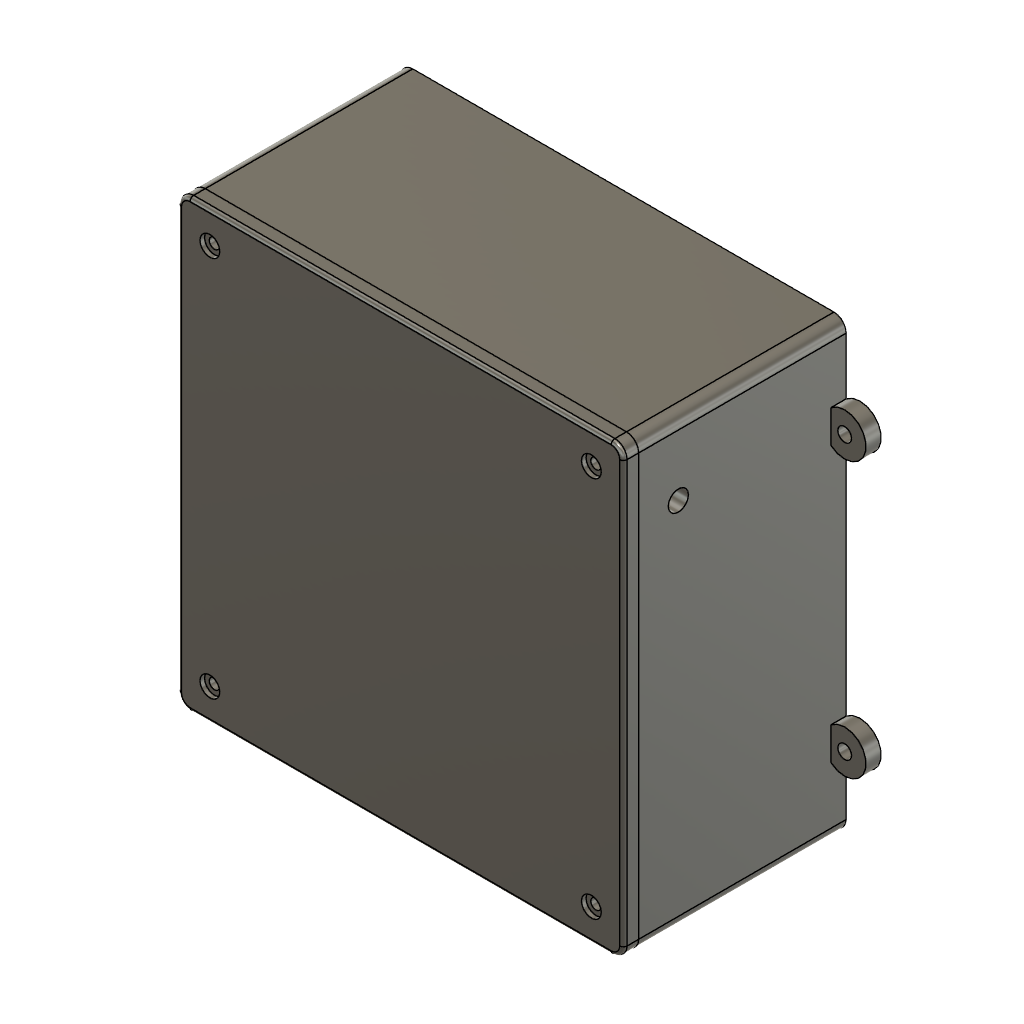
box-hybrid-lora_v1.0.0 (Autodesk Fusion 360 design; units mm, degrees)
part number: 2026-10-20-17-32-16-091
part number: 2026-10-20-17-32-16-274
part number: 2026-10-20-17-32-18-311
Autodesk Fusion 360 part; units mm, degrees
sketch "Outside footprint" plane through (0, 0, 0) normal (0, 0, 1) x (1, 0, 0) in component "01 Body - antenna, gasket groove and fasteners"
  line L0 (0, 0) -> (146, 0)
  line L1 (146, 0) -> (146, 146)
  line L2 (146, 146) -> (0, 146)
  line L3 (0, 146) -> (0, 0)
  dimension "d26" = 146
  dimension "d27" = 146
  constraint coincident L0.start L3.end
  measures "d26" horizontal distance of L0.start L0.end
  measures "d27" vertical distance of L0.end L1.end
extrude "Body outside" add sketch "Outside footprint" along normal blind 68 makes body 1 in component "01 Body - antenna, gasket groove and fasteners"
fillet "Four outside corner fillets" radius 4 4 edges at (0, 146, 34) (146, 146, 34) (146, 0, 34) (0, 0, 34) on bodies 1 in component "01 Body - antenna, gasket groove and fasteners"
shell "Open body - 5 mm walls and bottom" thickness 5 removed faces 1 at (94.6667, 50, 68) on bodies 1 in component "01 Body - antenna, gasket groove and fasteners"
ref_plane "WorkPlane1" through (0, 0, 64) normal (0, 0, 1) x (1, 0, 0) in component "01 Body - antenna, gasket groove and fasteners"
sketch "Rim supports screw posts and gasket channel" plane through (0, 0, 64) normal (0, 0, 1) x (1, 0, 0) in component "01 Body - antenna, gasket groove and fasteners"
  line L0 (2, 2) -> (144, 2)
  line L1 (144, 2) -> (144, 144)
  line L2 (144, 144) -> (2, 144)
  line L3 (2, 144) -> (2, 2)
  line L4 (20, 20) -> (126, 20)
  line L5 (126, 20) -> (126, 126)
  line L6 (126, 126) -> (20, 126)
  line L7 (20, 126) -> (20, 20)
extrude "Internal rim with 106 mm PCB insertion opening" add sketch "Rim supports screw posts and gasket channel" along normal blind 4 bodies 1 in component "01 Body - antenna, gasket groove and fasteners"
ref_plane "WorkPlane2" through (0, 0, 68) normal (0, 0, 1) x (1, 0, 0) in component "01 Body - antenna, gasket groove and fasteners"
sketch "Gasket channel - provisional 2 mm cord" plane through (0, 0, 68) normal (0, 0, 1) x (1, 0, 0) in component "01 Body - antenna, gasket groove and fasteners"
  line L0 (16.2, 16.2) -> (129.8, 16.2)
  line L1 (129.8, 16.2) -> (129.8, 129.8)
  line L2 (129.8, 129.8) -> (16.2, 129.8)
  line L3 (16.2, 129.8) -> (16.2, 16.2)
  line L4 (18.4, 18.4) -> (127.6, 18.4)
  line L5 (127.6, 18.4) -> (127.6, 127.6)
  line L6 (127.6, 127.6) -> (18.4, 127.6)
  line L7 (18.4, 127.6) -> (18.4, 18.4)
extrude "Continuous gasket groove in body rim" cut sketch "Gasket channel - provisional 2 mm cord" against normal blind 1.5 bodies 1 in component "01 Body - antenna, gasket groove and fasteners"
sketch "Mount 1 footprint - provisional X" plane through (0, 0, 0) normal (0, 0, 1) x (1, 0, 0) in component "01 Body - antenna, gasket groove and fasteners"
  circle A0 centre (25.436, 25.436) radius 2.5
  dimension "d41" = 5
  measures "d41" diameter of A0
extrude "PCB boss 1 - outside diameter 5 mm" add sketch "Mount 1 footprint - provisional X" along normal blind 10 bodies 1 in component "01 Body - antenna, gasket groove and fasteners"
sketch "Mount 2 footprint - provisional X" plane through (0, 0, 0) normal (0, 0, 1) x (1, 0, 0) in component "01 Body - antenna, gasket groove and fasteners"
  circle A0 centre (120.564, 25.436) radius 2.5
  dimension "d44" = 5
  measures "d44" diameter of A0
extrude "PCB boss 2 - outside diameter 5 mm" add sketch "Mount 2 footprint - provisional X" along normal blind 10 bodies 1 in component "01 Body - antenna, gasket groove and fasteners"
sketch "Mount 3 footprint - provisional X" plane through (0, 0, 0) normal (0, 0, 1) x (1, 0, 0) in component "01 Body - antenna, gasket groove and fasteners"
  circle A0 centre (25.436, 120.115) radius 2.5
  dimension "d47" = 5
  measures "d47" diameter of A0
extrude "PCB boss 3 - outside diameter 5 mm" add sketch "Mount 3 footprint - provisional X" along normal blind 10 bodies 1 in component "01 Body - antenna, gasket groove and fasteners"
sketch "Mount 4 footprint - provisional X" plane through (0, 0, 0) normal (0, 0, 1) x (1, 0, 0) in component "01 Body - antenna, gasket groove and fasteners"
  circle A0 centre (120.564, 120.115) radius 2.5
  dimension "d50" = 5
  measures "d50" diameter of A0
extrude "PCB boss 4 - outside diameter 5 mm" add sketch "Mount 4 footprint - provisional X" along normal blind 10 bodies 1 in component "01 Body - antenna, gasket groove and fasteners"
ref_plane "WorkPlane3" through (0, 0, 10) normal (0, 0, 1) x (1, 0, 0) in component "01 Body - antenna, gasket groove and fasteners"
sketch "Mount 1 blind hole" plane through (0, 0, 10) normal (0, 0, 1) x (1, 0, 0) in component "01 Body - antenna, gasket groove and fasteners"
  circle A0 centre (25.436, 25.436) radius 1
  dimension "d55" = 2
  measures "d55" diameter of A0
extrude "PCB hole 1 - diameter 2 mm, blind" cut sketch "Mount 1 blind hole" against normal blind 4 bodies 1 in component "01 Body - antenna, gasket groove and fasteners"
sketch "Mount 2 blind hole" plane through (0, 0, 10) normal (0, 0, 1) x (1, 0, 0) in component "01 Body - antenna, gasket groove and fasteners"
  circle A0 centre (120.564, 25.436) radius 1
  dimension "d58" = 2
  measures "d58" diameter of A0
extrude "PCB hole 2 - diameter 2 mm, blind" cut sketch "Mount 2 blind hole" against normal blind 4 bodies 1 in component "01 Body - antenna, gasket groove and fasteners"
sketch "Mount 3 blind hole" plane through (0, 0, 10) normal (0, 0, 1) x (1, 0, 0) in component "01 Body - antenna, gasket groove and fasteners"
  circle A0 centre (25.436, 120.115) radius 1
  dimension "d61" = 2
  measures "d61" diameter of A0
extrude "PCB hole 3 - diameter 2 mm, blind" cut sketch "Mount 3 blind hole" against normal blind 4 bodies 1 in component "01 Body - antenna, gasket groove and fasteners"
sketch "Mount 4 blind hole" plane through (0, 0, 10) normal (0, 0, 1) x (1, 0, 0) in component "01 Body - antenna, gasket groove and fasteners"
  circle A0 centre (120.564, 120.115) radius 1
  dimension "d64" = 2
  measures "d64" diameter of A0
extrude "PCB hole 4 - diameter 2 mm, blind" cut sketch "Mount 4 blind hole" against normal blind 4 bodies 1 in component "01 Body - antenna, gasket groove and fasteners"
sketch "Lid screw post 1 footprint" plane through (0, 0, 0) normal (0, 0, 1) x (1, 0, 0) in component "01 Body - antenna, gasket groove and fasteners"
  circle A0 centre (10.5, 10.5) radius 4.5
  dimension "d67" = 9
  measures "d67" diameter of A0
extrude "Lid screw post 1" add sketch "Lid screw post 1 footprint" along normal blind 68 bodies 1 in component "01 Body - antenna, gasket groove and fasteners"
sketch "Lid screw post 2 footprint" plane through (0, 0, 0) normal (0, 0, 1) x (1, 0, 0) in component "01 Body - antenna, gasket groove and fasteners"
  circle A0 centre (135.5, 10.5) radius 4.5
  dimension "d70" = 9
  measures "d70" diameter of A0
extrude "Lid screw post 2" add sketch "Lid screw post 2 footprint" along normal blind 68 bodies 1 in component "01 Body - antenna, gasket groove and fasteners"
sketch "Lid screw post 3 footprint" plane through (0, 0, 0) normal (0, 0, 1) x (1, 0, 0) in component "01 Body - antenna, gasket groove and fasteners"
  circle A0 centre (10.5, 135.5) radius 4.5
  dimension "d73" = 9
  measures "d73" diameter of A0
extrude "Lid screw post 3" add sketch "Lid screw post 3 footprint" along normal blind 68 bodies 1 in component "01 Body - antenna, gasket groove and fasteners"
sketch "Lid screw post 4 footprint" plane through (0, 0, 0) normal (0, 0, 1) x (1, 0, 0) in component "01 Body - antenna, gasket groove and fasteners"
  circle A0 centre (135.5, 135.5) radius 4.5
  dimension "d76" = 9
  measures "d76" diameter of A0
extrude "Lid screw post 4" add sketch "Lid screw post 4 footprint" along normal blind 68 bodies 1 in component "01 Body - antenna, gasket groove and fasteners"
ref_plane "WorkPlane4" through (0, 0, 68) normal (0, 0, 1) x (1, 0, 0) in component "01 Body - antenna, gasket groove and fasteners"
sketch "Lid screw pilot 1" plane through (0, 0, 68) normal (0, 0, 1) x (1, 0, 0) in component "01 Body - antenna, gasket groove and fasteners"
  circle A0 centre (10.5, 10.5) radius 1.25
  dimension "d81" = 2.5
  measures "d81" diameter of A0
extrude "Lid screw blind pilot 1" cut sketch "Lid screw pilot 1" against normal blind 12 bodies 1 in component "01 Body - antenna, gasket groove and fasteners"
sketch "Lid screw pilot 2" plane through (0, 0, 68) normal (0, 0, 1) x (1, 0, 0) in component "01 Body - antenna, gasket groove and fasteners"
  circle A0 centre (135.5, 10.5) radius 1.25
  dimension "d84" = 2.5
  measures "d84" diameter of A0
extrude "Lid screw blind pilot 2" cut sketch "Lid screw pilot 2" against normal blind 12 bodies 1 in component "01 Body - antenna, gasket groove and fasteners"
sketch "Lid screw pilot 3" plane through (0, 0, 68) normal (0, 0, 1) x (1, 0, 0) in component "01 Body - antenna, gasket groove and fasteners"
  circle A0 centre (10.5, 135.5) radius 1.25
  dimension "d87" = 2.5
  measures "d87" diameter of A0
extrude "Lid screw blind pilot 3" cut sketch "Lid screw pilot 3" against normal blind 12 bodies 1 in component "01 Body - antenna, gasket groove and fasteners"
sketch "Lid screw pilot 4" plane through (0, 0, 68) normal (0, 0, 1) x (1, 0, 0) in component "01 Body - antenna, gasket groove and fasteners"
  circle A0 centre (135.5, 135.5) radius 1.25
  dimension "d90" = 2.5
  measures "d90" diameter of A0
extrude "Lid screw blind pilot 4" cut sketch "Lid screw pilot 4" against normal blind 12 bodies 1 in component "01 Body - antenna, gasket groove and fasteners"
sketch "Outer mounting ear 1" plane through (0, 0, 0) normal (0, 0, 1) x (1, 0, 0) in component "01 Body - antenna, gasket groove and fasteners"
  circle A0 centre (-4.5, 28) radius 7
  dimension "d93" = 14
  measures "d93" diameter of A0
extrude "Mounting ear 1" add sketch "Outer mounting ear 1" along normal blind 5 bodies 1 in component "01 Body - antenna, gasket groove and fasteners"
sketch "Outer mounting ear 2" plane through (0, 0, 0) normal (0, 0, 1) x (1, 0, 0) in component "01 Body - antenna, gasket groove and fasteners"
  circle A0 centre (-4.5, 118) radius 7
  dimension "d96" = 14
  measures "d96" diameter of A0
extrude "Mounting ear 2" add sketch "Outer mounting ear 2" along normal blind 5 bodies 1 in component "01 Body - antenna, gasket groove and fasteners"
sketch "Outer mounting ear 3" plane through (0, 0, 0) normal (0, 0, 1) x (1, 0, 0) in component "01 Body - antenna, gasket groove and fasteners"
  circle A0 centre (150.5, 28) radius 7
  dimension "d99" = 14
  measures "d99" diameter of A0
extrude "Mounting ear 3" add sketch "Outer mounting ear 3" along normal blind 5 bodies 1 in component "01 Body - antenna, gasket groove and fasteners"
sketch "Outer mounting ear 4" plane through (0, 0, 0) normal (0, 0, 1) x (1, 0, 0) in component "01 Body - antenna, gasket groove and fasteners"
  circle A0 centre (150.5, 118) radius 7
  dimension "d102" = 14
  measures "d102" diameter of A0
extrude "Mounting ear 4" add sketch "Outer mounting ear 4" along normal blind 5 bodies 1 in component "01 Body - antenna, gasket groove and fasteners"
ref_plane "WorkPlane5" through (0, 0, 5) normal (0, 0, 1) x (1, 0, 0) in component "01 Body - antenna, gasket groove and fasteners"
sketch "Outer mounting hole 1" plane through (0, 0, 5) normal (0, 0, 1) x (1, 0, 0) in component "01 Body - antenna, gasket groove and fasteners"
  circle A0 centre (-4.5, 28) radius 2.25
  dimension "d107" = 4.5
  measures "d107" diameter of A0
extrude "Ear through hole 1" cut sketch "Outer mounting hole 1" against normal blind 5 bodies 1 in component "01 Body - antenna, gasket groove and fasteners"
sketch "Outer mounting hole 2" plane through (0, 0, 5) normal (0, 0, 1) x (1, 0, 0) in component "01 Body - antenna, gasket groove and fasteners"
  circle A0 centre (-4.5, 118) radius 2.25
  dimension "d110" = 4.5
  measures "d110" diameter of A0
extrude "Ear through hole 2" cut sketch "Outer mounting hole 2" against normal blind 5 bodies 1 in component "01 Body - antenna, gasket groove and fasteners"
sketch "Outer mounting hole 3" plane through (0, 0, 5) normal (0, 0, 1) x (1, 0, 0) in component "01 Body - antenna, gasket groove and fasteners"
  circle A0 centre (150.5, 28) radius 2.25
  dimension "d113" = 4.5
  measures "d113" diameter of A0
extrude "Ear through hole 3" cut sketch "Outer mounting hole 3" against normal blind 5 bodies 1 in component "01 Body - antenna, gasket groove and fasteners"
sketch "Outer mounting hole 4" plane through (0, 0, 5) normal (0, 0, 1) x (1, 0, 0) in component "01 Body - antenna, gasket groove and fasteners"
  circle A0 centre (150.5, 118) radius 2.25
  dimension "d116" = 4.5
  measures "d116" diameter of A0
extrude "Ear through hole 4" cut sketch "Outer mounting hole 4" against normal blind 5 bodies 1 in component "01 Body - antenna, gasket groove and fasteners"
ref_plane "WorkPlane6" through (146, 0, 0) normal (1, 0, 0) x (0, 1, 0) in component "01 Body - antenna, gasket groove and fasteners"
sketch "SMA bulkhead at upper right - test opening" plane through (146, 0, 0) normal (1, 0, 0) x (0, 0, -1) in component "01 Body - antenna, gasket groove and fasteners"
  circle A0 centre (-55, 122) radius 3.3
  dimension "d121" = 6.6
  measures "d121" diameter of A0
extrude "SMA bulkhead through wall - test fit" cut sketch "SMA bulkhead at upper right - test opening" along normal mid plane 10 bodies 1 in component "01 Body - antenna, gasket groove and fasteners"
sketch "Lid footprint" plane through (0, 0, 0) normal (0, 0, 1) x (1, 0, 0) in component "02 Lid - rounded top and four screw holes"
  line L0 (0, 0) -> (146, 0)
  line L1 (146, 0) -> (146, 146)
  line L2 (146, 146) -> (0, 146)
  line L3 (0, 146) -> (0, 0)
  dimension "d124" = 146
  dimension "d125" = 146
  constraint coincident L0.start L3.end
  measures "d124" horizontal distance of L0.start L0.end
  measures "d125" vertical distance of L0.end L1.end
extrude "Flat lid placeholder" add sketch "Lid footprint" along normal blind 5 separate body makes body 2 in component "02 Lid - rounded top and four screw holes"
fillet "Four outside corner fillets'" radius 4 4 edges at (0, 146, 2.5) (146, 146, 2.5) (146, 0, 2.5) (0, 0, 2.5) on bodies 2 in component "02 Lid - rounded top and four screw holes"
fillet "Soft rounded top edge of lid" radius 1.2 8 edges at (1.1716, 1.1716, 5) (0, 73, 5) (73, 0, 5) (144.8284, 1.1716, 5) (146, 73, 5) (144.8284, 144.8284, 5) (73, 146, 5) (1.1716, 144.8284, 5) on bodies 2 in component "02 Lid - rounded top and four screw holes"
ref_plane "WorkPlane1" through (0, 0, 5) normal (0, 0, 1) x (1, 0, 0) in component "02 Lid - rounded top and four screw holes"
sketch "Lid clearance hole 1" plane through (0, 0, 5) normal (0, 0, 1) x (1, 0, 0) in component "02 Lid - rounded top and four screw holes"
  circle A0 centre (10.5, 10.5) radius 1.7
  dimension "d134" = 3.4
  measures "d134" diameter of A0
extrude "Lid screw through hole 1" cut sketch "Lid clearance hole 1" against normal blind 5 bodies 2 in component "02 Lid - rounded top and four screw holes"
sketch "Lid screw head recess 1" plane through (0, 0, 5) normal (0, 0, 1) x (1, 0, 0) in component "02 Lid - rounded top and four screw holes"
  circle A0 centre (10.5, 10.5) radius 3.25
  dimension "d137" = 6.5
  measures "d137" diameter of A0
extrude "Lid screw head recess 1 (1)" cut sketch "Lid screw head recess 1" against normal blind 1.5 bodies 2 in component "02 Lid - rounded top and four screw holes"
sketch "Lid clearance hole 2" plane through (0, 0, 5) normal (0, 0, 1) x (1, 0, 0) in component "02 Lid - rounded top and four screw holes"
  circle A0 centre (135.5, 10.5) radius 1.7
  dimension "d140" = 3.4
  measures "d140" diameter of A0
extrude "Lid screw through hole 2" cut sketch "Lid clearance hole 2" against normal blind 5 bodies 2 in component "02 Lid - rounded top and four screw holes"
sketch "Lid screw head recess 2" plane through (0, 0, 5) normal (0, 0, 1) x (1, 0, 0) in component "02 Lid - rounded top and four screw holes"
  circle A0 centre (135.5, 10.5) radius 3.25
  dimension "d143" = 6.5
  measures "d143" diameter of A0
extrude "Lid screw head recess 2 (1)" cut sketch "Lid screw head recess 2" against normal blind 1.5 bodies 2 in component "02 Lid - rounded top and four screw holes"
sketch "Lid clearance hole 3" plane through (0, 0, 5) normal (0, 0, 1) x (1, 0, 0) in component "02 Lid - rounded top and four screw holes"
  circle A0 centre (10.5, 135.5) radius 1.7
  dimension "d146" = 3.4
  measures "d146" diameter of A0
extrude "Lid screw through hole 3" cut sketch "Lid clearance hole 3" against normal blind 5 bodies 2 in component "02 Lid - rounded top and four screw holes"
sketch "Lid screw head recess 3" plane through (0, 0, 5) normal (0, 0, 1) x (1, 0, 0) in component "02 Lid - rounded top and four screw holes"
  circle A0 centre (10.5, 135.5) radius 3.25
  dimension "d149" = 6.5
  measures "d149" diameter of A0
extrude "Lid screw head recess 3 (1)" cut sketch "Lid screw head recess 3" against normal blind 1.5 bodies 2 in component "02 Lid - rounded top and four screw holes"
sketch "Lid clearance hole 4" plane through (0, 0, 5) normal (0, 0, 1) x (1, 0, 0) in component "02 Lid - rounded top and four screw holes"
  circle A0 centre (135.5, 135.5) radius 1.7
  dimension "d152" = 3.4
  measures "d152" diameter of A0
extrude "Lid screw through hole 4" cut sketch "Lid clearance hole 4" against normal blind 5 bodies 2 in component "02 Lid - rounded top and four screw holes"
sketch "Lid screw head recess 4" plane through (0, 0, 5) normal (0, 0, 1) x (1, 0, 0) in component "02 Lid - rounded top and four screw holes"
  circle A0 centre (135.5, 135.5) radius 3.25
  dimension "d155" = 6.5
  measures "d155" diameter of A0
extrude "Lid screw head recess 4 (1)" cut sketch "Lid screw head recess 4" against normal blind 1.5 bodies 2 in component "02 Lid - rounded top and four screw holes"
component "01 Body - antenna, gasket groove and fasteners" placed x (1, 0, 0) y (0, 1, 0) z (0, 0, 1) at (0, 0, 0)
component "02 Lid - rounded top and four screw holes" placed x (1, 0, 0) y (0, 1, 0) z (0, 0, 1) at (0, 0, 68)
equation "box_length = 146 mm" comment "Temporary outside length"
equation "box_width = 146 mm" comment "Temporary outside width"
equation "body_height = 68 mm" comment "Temporary body height"
equation "lid_thickness = 5 mm" comment "Temporary lid thickness"
equation "wall_thickness = 5 mm" comment "Temporary wall and bottom thickness"
equation "corner_radius = 4 mm" comment "Temporary outside corner radius"
equation "lid_top_radius = 1.2 mm" comment "Rounded top edge of lid"
equation "pcb_standoff_height = 5 mm" comment "Temporary rise above the inner floor"
equation "boss_diameter = 5 mm" comment "Temporary PCB support outside diameter"
equation "mount_hole_diameter = 2 mm" comment "Blind hole matching PCB nominal diameter"
equation "lid_post_diameter = 9 mm" comment "Four independent lid screw posts"
equation "lid_pilot_diameter = 2.5 mm" comment "Trial pilot for M3 fastener; test with actual screw"
equation "lid_pilot_depth = 12 mm" comment "Blind lid screw engagement"
equation "lid_clearance_diameter = 3.4 mm" comment "Trial lid screw clearance"
equation "lid_head_recess_diameter = 6.5 mm" comment "Trial screw head recess"
equation "lid_head_recess_depth = 1.5 mm" comment "Trial screw head recess depth"
equation "gasket_cord_diameter = 2 mm" comment "Trial cord only; actual cord not selected"
equation "gasket_groove_width = 2.2 mm" comment "Trial groove width; square path outside the PCB envelope"
equation "gasket_groove_depth = 1.5 mm" comment "Trial groove depth"
equation "antenna_panel_hole = 6.6 mm" comment "Trial SMA opening; measure actual connector"
equation "ear_diameter = 14 mm" comment "Outside mounting ear diameter"
equation "ear_hole_diameter = 4.5 mm" comment "Trial mounting screw clearance"
equation "ear_thickness = 5 mm" comment "Mounting ear thickness"
equation "pcb_length_ref = 100 mm" comment "PCB reference only; mounting is pending"
equation "pcb_width_ref = 100 mm" comment "PCB reference only; mounting is pending"
equation "d26 = box_length"
equation "d27 = box_width"
equation "d28 = body_height"
equation "d31 = corner_radius"
equation "d32 = wall_thickness"
equation "d33 = body_height - 4 mm"
equation "d37 = body_height"
equation "d39 = -gasket_groove_depth"
equation "d41 = boss_diameter"
equation "d42 = wall_thickness + pcb_standoff_height"
equation "d44 = boss_diameter"
equation "d45 = wall_thickness + pcb_standoff_height"
equation "d47 = boss_diameter"
equation "d48 = wall_thickness + pcb_standoff_height"
equation "d50 = boss_diameter"
equation "d51 = wall_thickness + pcb_standoff_height"
equation "d53 = wall_thickness + pcb_standoff_height"
equation "d55 = mount_hole_diameter"
equation "d58 = mount_hole_diameter"
equation "d61 = mount_hole_diameter"
equation "d64 = mount_hole_diameter"
equation "d67 = lid_post_diameter"
equation "d68 = body_height"
equation "d70 = lid_post_diameter"
equation "d71 = body_height"
equation "d73 = lid_post_diameter"
equation "d74 = body_height"
equation "d76 = lid_post_diameter"
equation "d77 = body_height"
equation "d79 = body_height"
equation "d81 = lid_pilot_diameter"
equation "d82 = -lid_pilot_depth"
equation "d84 = lid_pilot_diameter"
equation "d85 = -lid_pilot_depth"
equation "d87 = lid_pilot_diameter"
equation "d88 = -lid_pilot_depth"
equation "d90 = lid_pilot_diameter"
equation "d91 = -lid_pilot_depth"
equation "d93 = ear_diameter"
equation "d94 = ear_thickness"
equation "d96 = ear_diameter"
equation "d97 = ear_thickness"
equation "d99 = ear_diameter"
equation "d100 = ear_thickness"
equation "d102 = ear_diameter"
equation "d103 = ear_thickness"
equation "d105 = ear_thickness"
equation "d107 = ear_hole_diameter"
equation "d108 = -ear_thickness"
equation "d110 = ear_hole_diameter"
equation "d111 = -ear_thickness"
equation "d113 = ear_hole_diameter"
equation "d114 = -ear_thickness"
equation "d116 = ear_hole_diameter"
equation "d117 = -ear_thickness"
equation "d119 = box_length"
equation "d121 = antenna_panel_hole"
equation "d122 = 2 * wall_thickness"
equation "d124 = box_length"
equation "d125 = box_width"
equation "d126 = lid_thickness"
equation "d129 = corner_radius"
equation "d131 = lid_top_radius"
equation "d132 = lid_thickness"
equation "d134 = lid_clearance_diameter"
equation "d135 = -lid_thickness"
equation "d137 = lid_head_recess_diameter"
equation "d138 = -lid_head_recess_depth"
equation "d140 = lid_clearance_diameter"
equation "d141 = -lid_thickness"
equation "d143 = lid_head_recess_diameter"
equation "d144 = -lid_head_recess_depth"
equation "d146 = lid_clearance_diameter"
equation "d147 = -lid_thickness"
equation "d149 = lid_head_recess_diameter"
equation "d150 = -lid_head_recess_depth"
equation "d152 = lid_clearance_diameter"
equation "d153 = -lid_thickness"
equation "d155 = lid_head_recess_diameter"
equation "d156 = -lid_head_recess_depth"
named bodies: "Body with mounting features", "Rounded screw lid - no gasket"
